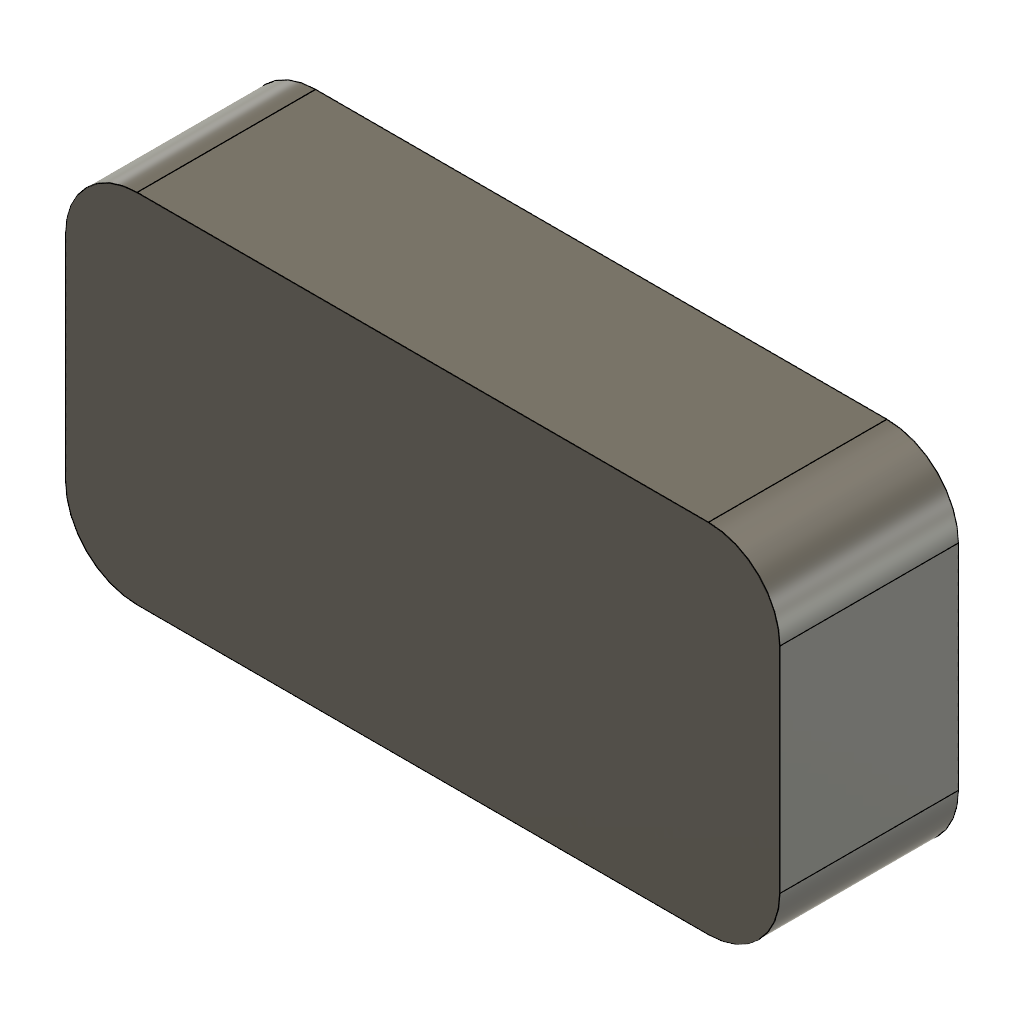
fillet_vertical_edges (Autodesk Fusion 360 design; units mm, degrees)
part number: 2026-11-10-15-06-53-951
Autodesk Fusion 360 part; units mm, degrees
sketch "Sketch1" plane through (0, 0, 0) normal (0, 0, 1) x (1, 0, 0)
  line L0 (0, 0) -> (20, 0)
  line L1 (20, 0) -> (20, 10)
  line L2 (20, 10) -> (0, 10)
  line L3 (0, 10) -> (0, 0)
extrude "Extrude1" add sketch "Sketch1" along normal blind 5
fillet "Fillet1" radius 2 4 edges at (0, 10, 2.5) (20, 10, 2.5) (20, 0, 2.5) (0, 0, 2.5)
